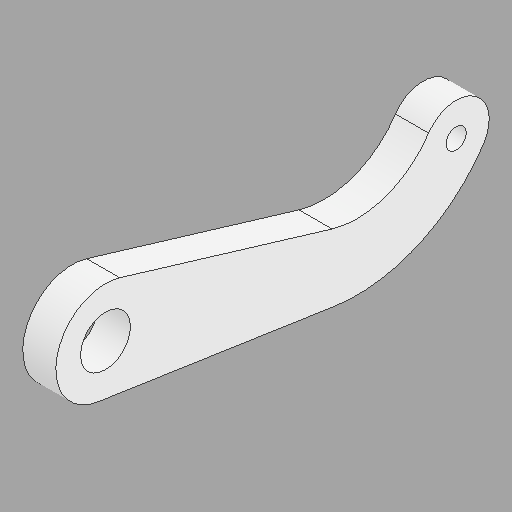
# Autodesk Inventor part: thigh_link_passive
Saved by Autodesk Inventor 2025 (Build 290162000, 162)
## iProperties
Created: 2024-11-05
Part Number: thigh_link_passive
Material: 일반
Document SubType Name: Modeling
Designer: OSB
Density: 0.651086 g/cm^3
Appearance: 기본값
Mass: 19 g
Surface Area: 95.5796 cm^2
Volume: 29.182 cm^3
Author: OSB
Autodesk Inventor part; units mm, degrees
ref_plane "YZ Plane" through (0, 0, 0) normal (1, 0, 0) x (0, 1, 0)
ref_plane "XZ Plane" through (0, 0, 0) normal (0, 1, 0) x (-1, 0, 0)
ref_plane "XY Plane" through (0, 0, 0) normal (0, 0, 1) x (1, 0, 0)
sketch "스케치1" plane through (0, 0, 0) normal (0, 1, 0) x (-1, 0, 0)
  circle A0 centre (0, 0) radius 15
  circle A1 centre (106, 0) radius 3.1
  circle A2 centre (106, 0) radius 10
  line L0 (4.3232, 14.3635) -> (68.4905, -4.9499)
  arc A3 (68.4905, -4.9499) -> (97.6795, 5.547) centre (76, 20) ccw
  arc A4 (69.1663, -25.5457) -> (114.3205, -5.547) centre (76, 20) ccw
  line L1 (-2.2257, -14.834) -> (69.1663, -25.5457)
  circle A5 centre (0, 0) radius 7.55
  point P0 (106, 10)
  dimension "d1" = 30
  dimension "d2" = 6.2
  dimension "d3" = 20
  dimension "d4" = 106
  dimension "d18" = 30
  dimension "d19" = 20
  dimension "d26" = 15.1
  constraints: 9 point on circle, 6 centre point, 6 tangent, 4 end point, 3 coincident, 1 horizontal alignment
  measures "d1" diameter of A0
  measures "d2" diameter of A1
  measures "d3" diameter of A2
  measures "d4" distance of A1.centre point (0, 0)
  measures "d18" horizontal distance of A1.centre A3.centre
  measures "d19" vertical distance of A1.centre A3.centre
  measures "d26" diameter of A5
extrude "돌출1" add sketch "스케치1" along normal blind 10
